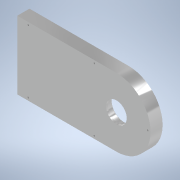
# Autodesk Inventor part: 1.5_2_MainBaseCover
Saved by Autodesk Inventor 2021 (Build 250183000, 183)
## iProperties
Created: 2025-11-20
Part Number: 1.5_2_MainBaseCover
Material: Aluminum 6061
Document SubType Name: Modeling
Designer: Admin
Density: 2.7 g/cm^3
Appearance: Aluminum - Flat
Mass: 12324.2 g
Surface Area: 4469.77 cm^2
Volume: 4564.51 cm^3
Author: Admin
Autodesk Inventor part; units mm, degrees
ref_plane "YZ Plane" through (0, 0, 0) normal (1, 0, 0) x (0, 1, 0)
ref_plane "XZ Plane" through (0, 0, 0) normal (0, 1, 0) x (-1, 0, 0)
ref_plane "XY Plane" through (0, 0, 0) normal (0, 0, 1) x (1, 0, 0)
sketch "Sketch1" plane through (0, 0, 0) normal (0, 0, 1) x (1, 0, 0)
  circle A0 centre (0, 0) radius 155
  line L0 (0, 155) -> (-450, 155)
  line L1 (-450, 155) -> (-450, -155)
  line L2 (-450, -155) -> (0, -155)
  dimension "d0" = 310
  dimension "d1" = 450
  constraints: 6 end point, 2 perpendicular, 2 point on circle, 2 tangent, 1 centre point, 1 coincident, 1 horizontal
  measures "d0" diameter of A0
  measures "d1" distance from line of point (0, 0) L1
extrude "Extrusion1" add sketch "Sketch1" along normal blind 35
sketch "Sketch14" plane through (0, 0, 0) normal (0, 0, -1) x (-1, 0, 0)
  line L0 (450, -155) -> (0, -155) projected
  arc A0 (0, 155) -> (0, -155) centre (0, 0) ccw projected
  line L1 (0, 155) -> (450, 155) projected
  line L2 (450, -115) -> (0, -115)
  arc A1 (0, 115) -> (0, -115) centre (0, 0) ccw
  line L3 (0, 115) -> (450, 115)
  line L4 (450, -115) -> (450, -155)
  line L5 (450, 155) -> (450, 115)
  dimension "d44" = 40
  constraints: 8 end point, 2 point on circle, 1 centre point, 1 point on line, 2 other
  measures "d44" distance between parallel lines of L0 L2
extrude "Extrusion7" add sketch "Sketch14" along normal blind 20
sketch "Sketch18" plane through (0, 0, 0) normal (0, 1, 0) x (-1, 0, 0)
  line L0 (0, 0) -> (0, -20) projected
  line L1 (0, -20) -> (0, 35) projected
  line L2 (0, 0) -> (0, 35)
  line L3 (0, 35) -> (47, 35)
  line L4 (0, 35) -> (450, 35) projected
  line L5 (47, 27) -> (55, 27)
  line L6 (55, 27) -> (55, 0)
  line L7 (450, 0) -> (0, 0) projected
  line L8 (0, 0) -> (55, 0)
  line L9 (47, 27) -> (47, 35)
  line L10 (0, -30) -> (0, 40) projected
  dimension "d58" = 47
  dimension "d73" = 55
  dimension "d74" = 27
  constraints: 12 end point, 3 perpendicular, 2 point on line, 1 horizontal, 1 vertical
  measures "d58" distance of L1.end L3.end
  measures "d73" distance between parallel lines of L1 L6
  measures "d74" distance from line of L5.end L7
revolve "Revolution5" cut sketch "Sketch18" angle 360 about axis through (0, 0, -10) along (0, 0, 1)
sketch "Sketch19" plane through (0, 0, 35) normal (0, 0, 1) x (1, 0, 0)
  line L0 (-450, -155) -> (0, -155) projected
  line L1 (0, 155) -> (-450, 155) projected
  arc A0 (0, -155) -> (0, 155) centre (0, 0) ccw projected
  line L2 (-450, -142.5) -> (0, -142.5)
  arc A1 (0, -142.5) -> (0, 142.5) centre (0, 0) ccw
  line L3 (0, 142.5) -> (-450, 142.5)
  line L4 (-400, -142.5) -> (-400, 142.5)
  line L5 (-100, 142.5) -> (-100, -142.5)
  line L6 (-450, 155) -> (-450, -155) projected
  line L7 (-571, 0) -> (276, 0) projected
  point P0 (0, 0)
  point P1 (142.5, 0)
  dimension "d62" = 12.5
  dimension "d63" = 50
  dimension "d64" = 300
  constraints: 8 end point, 5 point on line, 4 coincident, 3 point on circle, 1 centre point, 1 parallel, 1 perpendicular, 2 other
  measures "d62" distance between parallel lines of L0 L2
  measures "d63" distance between parallel lines of L6 L4
  measures "d64" distance between parallel lines of L5 L4
hole "Hole3" at (-400, -142.5, 35) at (-100, -142.5, 35) at (-100, 142.5, 35) at (-400, 142.5, 35) at (142.5, 0, 35) direction (0, 0, -1) diameter 6.647 end through all thread size "M8x1.25" class "6H" standard "ISO Metric profile"
chamfer "Chamfer1" distance 2 angle 45 1 edges at (55, 0, 0)
fillet "Fillet2" radius 0.5 1 edges at (55, 0, 27)
body "Solid1"
